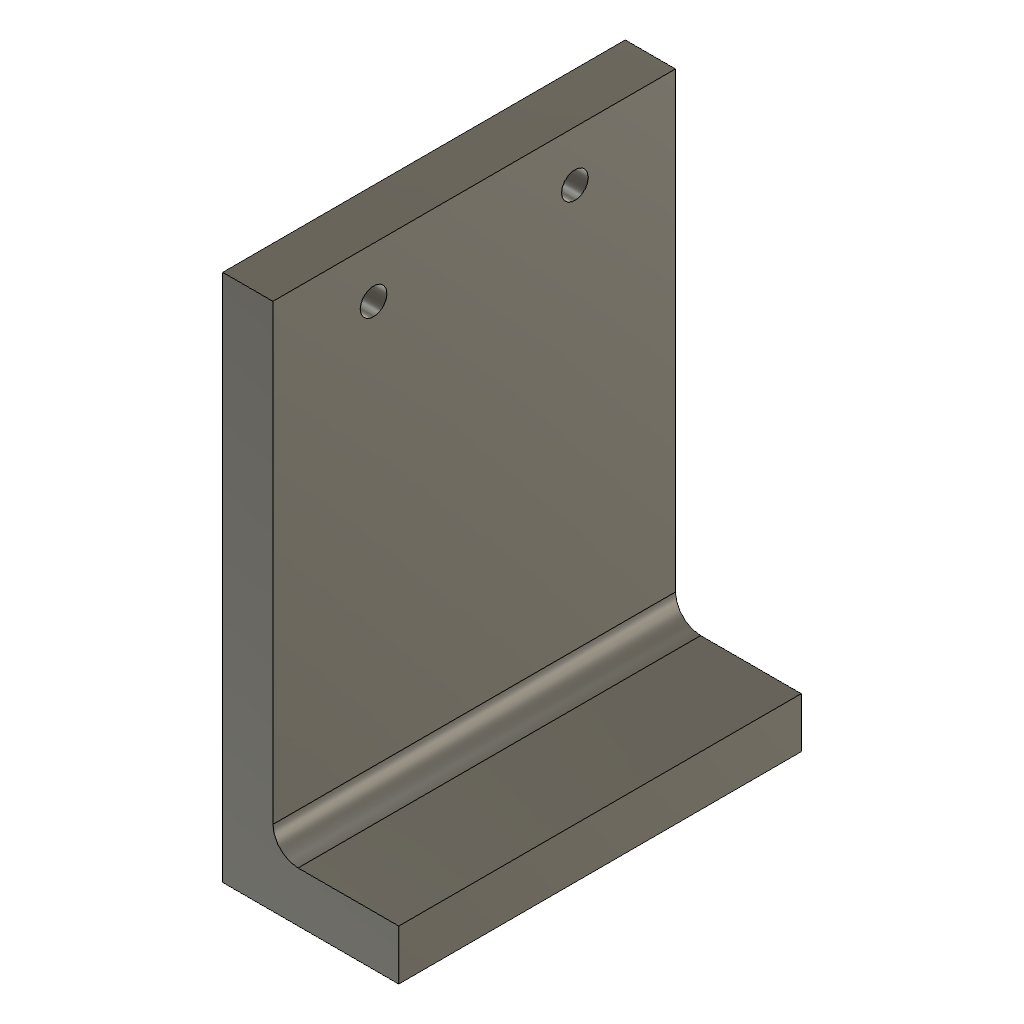
frame_leg (Autodesk Fusion 360 design; units mm, degrees)
part number: 2026-10-05-21-37-50-400
Autodesk Fusion 360 part; units mm, degrees
sketch "Sketch1" plane through (0, 0, 0) normal (0, 1, 0) x (1, 0, 0)
  line L0 (0, 0) -> (35, 0)
  line L1 (35, 0) -> (35, -10)
  line L2 (35, -10) -> (10, -10)
  line L3 (10, -10) -> (10, -105)
  line L4 (10, -105) -> (0, -105)
  line L5 (0, 0) -> (0, -105)
  dimension "d1" = 10
  dimension "d2" = 35
  dimension "d3" = 10
  dimension "d4" = 105
  constraint coincident L0.start L5.start
  constraint horizontal L0
  constraint perpendicular L0 L1
  constraint perpendicular L1 L2
  constraint perpendicular L2 L3
  constraint perpendicular L3 L4
  constraint perpendicular L4 L5
  measures "d1" distance of L0.end L1.end
  measures "d2" distance of L0.start L0.end
  measures "d3" distance of L3.end L4.end
  measures "d4" distance of L0.start L4.end
extrude "Extrude1" add sketch "Sketch1" along normal blind 80
sketch "Sketch2" plane through (10, 0, 0) normal (1, 0, 0) x (0, 1, 0)
  line L0 (0, 105) -> (0, 10)
  line L1 (0, 10) -> (80, 10)
  line L2 (80, 10) -> (80, 105)
  line L3 (80, 105) -> (0, 105)
  line L4 (0, 95) -> (80, 95) construction
  circle A0 centre (20, 95) radius 2.65
  circle A1 centre (60, 95) radius 2.65
  dimension "d7" = 10
  dimension "d8" = 5.3
  dimension "d9" = 5.3
  dimension "d10" = 20
  dimension "d11" = 20
  constraint coincident L0 L4.start
  constraint coincident L2 L4.end
  constraint perpendicular L2 L4
  constraint coincident L4 A0.centre
  constraint coincident L4 A1.centre
  measures "d7" distance of L3 L4
  measures "d8" diameter of A0
  measures "d9" diameter of A1
  measures "d10" distance of L0 A0.centre
  measures "d11" distance of L2 A1.centre
extrude "Extrude2" cut sketch "Sketch2" against normal blind 10 contours A0 | A1
fillet "Fillet1" radius 5 1 edges at (10, 40, 10)
